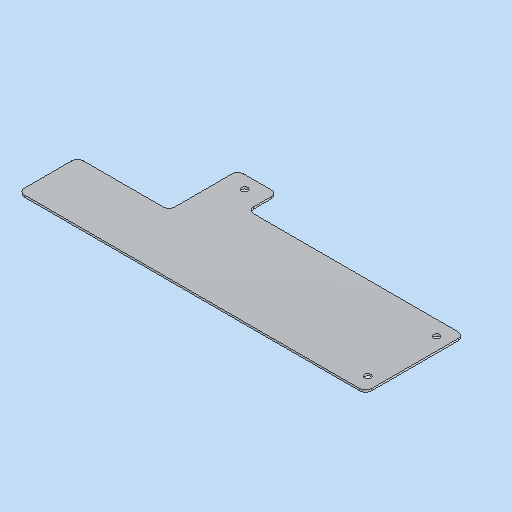
# Autodesk Inventor part: MM0948AN140_G01_122
Saved by Autodesk Inventor 2023.3 (Build 273359000, 359)
## iProperties
Created: 2023-08-11
Part Number: MM0948AN140_G01_122
Material: 3.3535 AlMg3 - AW 5754 (Blech)
Description: =<RBPARTNOTITLE2>
Document SubType Name: Sheet Metal
Designer: RIC7AN
Mass: 176.226 g
Surface Area: 673.081 cm^2
Volume: 65.2929 cm^3
Density: 2.699 g/cm^3
Sheet Metal Rule: Standard_mm
Appearance: Aluminium AnP
RBPARTMADEOF: 2 x 130 x 353 (FM)
RBDRAWINGMISSINGSPEC: --
AnP_Kategorie: 1
RBPARTNOTITLE2: Anfertigungsteil
RBSURFACE: --
RBPARTNOTITLE1: manufactured part
RBSURFACE2: eloxiert E6/EV1 aluminiumfarbig
AnP_Material: =<Material>
RBMATERIAL: =<Material>
RBMATNO: =<Part Number>
RBPARTNO: SIEHE MNR
MaxAbmaße: 2 x 130 x 353 (FM)
Author: RIC7AN
Keywords: =<RBPARTMADEOF>
Comments: =<RBSURFACE2>
Revision Number: 01
Autodesk Inventor part; units mm, degrees
ref_plane "YZ Plane" through (0, 0, 0) normal (1, 0, 0) x (0, 1, 0)
ref_plane "XZ Plane" through (0, 0, 0) normal (0, 1, 0) x (-1, 0, 0)
ref_plane "XY Plane" through (0, 0, 0) normal (0, 0, 1) x (1, 0, 0)
sketch "Skizze1" plane through (0, 0, 0) normal (0, 0, 1) x (1, 0, 0)
  line L0 (0, 0) -> (-260, 0)
  line L1 (-260, 0) -> (-260, 130)
  line L2 (-260, 130) -> (0, 130)
  line L3 (0, 130) -> (0, 0)
  line L4 (0, 130) -> (-220, 130)
  line L5 (-220, 130) -> (-220, 100)
  line L6 (-220, 100) -> (0, 100)
  line L7 (0, 100) -> (0, 130)
  line L8 (-260, 0) -> (-353, 0)
  line L9 (-353, 0) -> (-353, 60)
  line L10 (-353, 60) -> (-260, 60)
  line L11 (-260, 60) -> (-260, 0)
  point P0 (-220, 115)
  dimension "d0" = 30
  dimension "d1" = 130
  dimension "d2" = 260
  dimension "d3" = 40
  dimension "d17" = 93
  dimension "d18" = 60
  measures "d0" distance of L4.end L5.end
  measures "d1" distance of L0.end L1.end
  measures "d2" distance of L0.start L0.end
  measures "d3" distance from line of point (-220, 115) L1
  measures "d17" distance of L9.end L10.end
  measures "d18" distance of L8.end L9.end
extrude "Grobblech1" add sketch "Skizze1" along normal blind 2 contours L0 L1 L2 L5 L6 L3 | L8 L9 L10 L1
sketch "Skizze2" plane through (0, 0, 2) normal (0, 0, 1) x (1, 0, 0)
  line L0 (0, 100) -> (0, 0) projected
  line L1 (0, 100) -> (-220, 100) projected
  line L2 (-260, 130) -> (-220, 130) projected
  line L3 (-260, 60) -> (-260, 130) projected
  point P0 (-240, 117)
  point P1 (-13, 85)
  point P2 (-13, 15)
  point P3 (-260, 0)
  dimension "d5" = 13
  dimension "d6" = 70
  dimension "d7" = 15
  dimension "d8" = 13
  dimension "d9" = 20
  constraints: 1 vertical alignment
  measures "d5" distance from line of L0 point (-13, 85)
  measures "d6" distance of point (-13, 15) point (-13, 85)
  measures "d7" distance from line of L1 point (-13, 85)
  measures "d8" distance from line of L2 point (-240, 117)
  measures "d9" distance from line of point (-240, 117) L3
hole "Bohrung1" at (-240, 117, 2) at (-13, 85, 2) at (-13, 15, 2) direction (0, 0, -1) diameter 6.6 end through all clearance for "Inbusschraube ISO 4762  versenkt" size "M6" standard "ISO"
fillet "Eckenrundung1" radius 6 8 edges at (-260, 60, 1) (-260, 130, 1) (-220, 130, 1) (-220, 100, 1) (0, 100, 1) (0, 0, 1) (-353, 0, 1) (-353, 60, 1)
equation "\"d15\" = Stärke"
equation "\"d4\" = Stärke"
equation "\"Biegeradius\" = Stärke"
equation "\"BreiteBiegungsfreistellung\" = Stärke"
equation "\"TiefeBiegungsfreistellung\" = 0.5 * Stärke"
equation "\"GrößeEckenfreistellung\" = 4 * Stärke"
equation "\"MinimalRest\" = 2 * Stärke"
equation "\"Übergangsradius\" = Biegeradius"
equation "\"JacobiRadiusGröße\" = Biegeradius"
equation "\"Abstandsgröße\" = Stärke"
equation "\"Stärke\" = 2"
